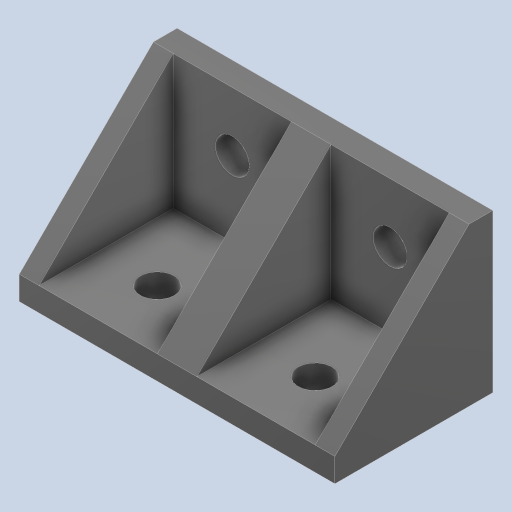
# Autodesk Inventor part: Cantoneira perfil alumínio
Saved by Autodesk Inventor 2024.3 (Build 283343000, 343)
## iProperties
Created: 2024-02-21
Part Number: Cantoneira perfil alumínio
Material: ABS plástico
Document SubType Name: Modeling
Designer: Cliente
Density: 0.964849 g/cm^3
Appearance: Suave - Branco
Mass: 5.51 g
Surface Area: 42.3535 cm^2
Volume: 5.71074 cm^3
Author: Cliente
Autodesk Inventor part; units mm, degrees
ref_plane "YZ Plane" through (0, 0, 0) normal (1, 0, 0) x (0, 1, 0)
ref_plane "XZ Plane" through (0, 0, 0) normal (0, 1, 0) x (-1, 0, 0)
ref_plane "XY Plane" through (0, 0, 0) normal (0, 0, 1) x (1, 0, 0)
sketch "Esboço1" plane through (0, 0, 0) normal (0, 0, 1) x (1, 0, 0)
  line L0 (-10, 20) -> (10, 20)
  line L1 (10, 20) -> (10, 0)
  line L2 (10, 0) -> (-10, 0)
  line L3 (-10, 0) -> (-10, 20)
  line L4 (-10, 0) -> (-10, 3)
  line L5 (-10, 3) -> (10, 3)
  line L6 (-7.5, 20) -> (7.5, 20)
  line L7 (7.5, 20) -> (7.5, 0)
  line L8 (-7.5, 20) -> (-7.5, 0)
  line L9 (0, 16) -> (0, 20)
  line L10 (-2.75, 17) -> (2.75, 17)
  line L11 (2.75, 17) -> (2.75, 18.5)
  line L12 (2.75, 18.5) -> (-2.75, 18.5)
  line L13 (-2.75, 18.5) -> (-2.75, 17)
  line L14 (-10, 10) -> (-7.5, 10)
  line L15 (-2.75, 3) -> (2.75, 3)
  line L16 (2.75, 3) -> (2.75, 1.5)
  line L17 (2.75, 1.5) -> (-2.75, 1.5)
  line L18 (-2.75, 1.5) -> (-2.75, 3)
  circle A0 centre (0, 12.5) radius 2.15
  point P0 (0, 0)
  point P1 (0, 0)
  point P2 (-7.5, 3)
  point P3 (-7.5, 20)
  point P4 (7.5, 20)
  point P5 (7.5, 3)
  point P6 (0, 17)
  point P7 (2.75, 3)
  point P8 (-2.75, 3)
  dimension "d0" = 20
  dimension "d1" = 20
  dimension "d4" = 3
  dimension "d5" = 15
  dimension "d17" = 5.5
  dimension "d18" = 1.5
  dimension "d19" = 1.5
  dimension "d32" = 4.3
  dimension "d33" = 7.5
  constraints: 38 end point, 6 midpoint, 5 perpendicular, 4 parallel, 4 point on line, 4 symmetric about line, 3 horizontal, 2 vertical alignment, 1 centre point, 1 coincident, 1 vertical
  measures "d0" distance of L1.end L2.end
  measures "d1" distance of L0.end L1.end
  measures "d4" distance of L2.end L4.end
  measures "d5" distance of L6.start L6.end
  measures "d17" distance of L12.end L11.end
  measures "d18" distance of L11.end L10.end
  measures "d19" distance between parallel lines of L6 L12
  measures "d32" diameter of A0
  measures "d33" distance from line of A0.centre L0
extrude "Extrusão1" add sketch "Esboço1" along normal blind 20 contours L0 L8 L14 L3 | L14 L8 L5 L3 | L5 L8 L2 L3 | L0 L1 L5 L7 | L5 L18 L17 L16 L7 L2 L8 | L5 L1 L2 L7 | L5 L16 L17 L18
extrude "Extrusão2" add sketch "Esboço1" along normal blind 3 contours L12 L11 L10 L9 | L9 L10 L13 L12 | L0 L7 L5 L8
chamfer "Chanfro1" distance 17 angle 45 2 edges at (8.75, 20, 20) (-8.75, 20, 20)
sketch "Esboço2" plane through (-10, 0, 0) normal (0, -1, 0) x (1, 0, 0)
  line L0 (20, 0) -> (20, 20) projected
  line L1 (0, 20) -> (20, 20) projected
  line L2 (7.25, 17) -> (12.75, 17)
  line L3 (12.75, 17) -> (12.75, 18.5)
  line L4 (12.75, 18.5) -> (7.25, 18.5)
  line L5 (7.25, 18.5) -> (7.25, 17)
  line L6 (13, 10) -> (20, 10)
  line L7 (7.25, 3) -> (12.75, 3)
  line L8 (12.75, 3) -> (12.75, 1.5)
  line L9 (12.75, 1.5) -> (7.25, 1.5)
  line L10 (7.25, 1.5) -> (7.25, 3)
  circle A0 centre (10, 12.5) radius 2.15
  line L11 (0, 0) -> (20, 0) projected
  point P0 (10, 0)
  point P1 (10, 20)
  point P2 (10, 18.5)
  point P3 (10, 20)
  point P4 (10, 0)
  dimension "d22" = 5.5
  dimension "d23" = 1.5
  dimension "d24" = 1.5
  dimension "d34" = 4.3
  dimension "d35" = 7.5
  constraints: 18 end point, 5 midpoint, 4 symmetric about line, 2 horizontal, 2 parallel, 2 vertical alignment, 1 centre point, 1 horizontal alignment, 1 perpendicular
  measures "d22" distance of L4.end L3.end
  measures "d23" distance of L3.end L2.end
  measures "d24" distance between parallel lines of L1 L4
  measures "d34" diameter of A0
  measures "d35" distance from line of L1 A0.centre
extrude "Extrusão3" cut sketch "Esboço2" against normal blind 3 contours A0
extrude "Extrusão4" [suppressed]
extrude "Extrusão5" [suppressed]
mirror "Espelhar1" about plane through (10, 0, 0) normal (1, 0, 0)
